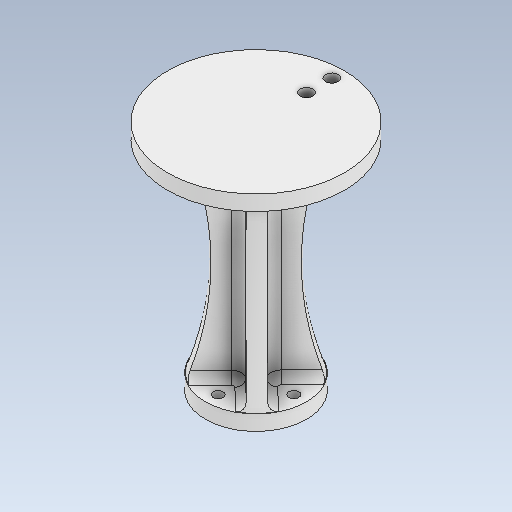
# Autodesk Inventor part: Load cell support
Saved by Autodesk Inventor 2026.2 (Build 302298010, 298A)
## iProperties
Created: 2026-04-30
Part Number: Load cell support
Material: ABS 플라스틱
Document SubType Name: Modeling
Designer: khw
Density: 1.06 g/cm^3
Appearance: 매끄러움 - 흰색
Author: khw
Autodesk Inventor part; units mm, degrees
ref_plane "YZ Plane" through (0, 0, 0) normal (1, 0, 0) x (0, 1, 0)
ref_plane "XZ Plane" through (0, 0, 0) normal (0, 1, 0) x (-1, 0, 0)
sketch "스케치1" plane through (0, 0, 0) normal (0, 1, 0) x (-1, 0, 0)
  circle A0 centre (0, 0) radius 20
  circle A1 centre (15, 0) radius 2
  line L0 (0, 0) -> (15, 0) construction
  circle A2 centre (0, 15) radius 2
  line L1 (0, 0) -> (0, 15) construction
  circle A3 centre (-15, 0) radius 2
  line L2 (0, 0) -> (-15, 0) construction
  circle A4 centre (0, -15) radius 2
  line L3 (0, 0) -> (0, -15) construction
  dimension "d0" = 4
  dimension "d1" = 15
  dimension "d2" = 40
  dimension "d5" = 360
  constraints: 8 end point, 5 centre point, 3 coincident, 1 horizontal, 15 other
  measures "d0" diameter of A1
  measures "d1" distance of L0.end point (0, 0)
  measures "d2" diameter of A0
extrude "돌출1" add sketch "스케치1" along normal blind 6
sketch "스케치2" plane through (0, 6, 0) normal (0, 1, 0) x (1, 0, 0)
  circle A0 centre (0, 0) radius 20 projected
  line L0 (-13.9405, -14.3409) -> (13.9405, 14.3409) construction
  line L1 (-11.6317, -16.2697) -> (15.9339, 12.0876)
  line L2 (-15.9339, -12.0876) -> (11.6317, 16.2697)
  line L3 (14.3409, -13.9405) -> (-14.3409, 13.9405) construction
  line L4 (16.2697, -11.6317) -> (-12.0876, 15.9339)
  line L5 (12.0876, -15.9339) -> (-16.2697, 11.6317)
  line L6 (13.9405, 14.3409) -> (-13.9405, -14.3409) construction
  line L7 (11.6317, 16.2697) -> (-15.9339, -12.0876)
  line L8 (15.9339, 12.0876) -> (-11.6317, -16.2697)
  line L9 (-14.3409, 13.9405) -> (14.3409, -13.9405) construction
  line L10 (-16.2697, 11.6317) -> (12.0876, -15.9339)
  line L11 (-12.0876, 15.9339) -> (16.2697, -11.6317)
  point P0 (-4.2422, -0.0601)
  point P1 (0.0601, -4.2422)
  point P2 (4.2422, 0.0601)
  point P3 (11.6317, 16.2697)
  point P4 (-0.0601, 4.2422)
  point P5 (-16.2697, 11.6317)
  dimension "d9" = 40
  dimension "d10" = 3
  dimension "d13" = 360
  constraints: 24 end point, 4 point on circle, 2 coincident, 2 symmetric about line, 1 parallel, 43 other
  measures "d9" distance of L0.start L0.end
  measures "d10" distance between parallel lines of L0 L1
extrude "돌출2" add sketch "스케치2" along normal blind 80 contours L1 L4 L2 A0 | A0 L5 L1 L4 | L1 L5 L2 L4 | L4 L2 L5 A0 | L1 A0 L2 L5
sketch "스케치3" plane through (0, 86, 0) normal (0, 1, 0) x (1, 0, 0)
  circle A0 centre (0, 0) radius 35
  circle A1 centre (0, 0) radius 20 projected
  line L0 (0, 0) -> (0, 35)
  circle A2 centre (0, 20) radius 2.5
  circle A3 centre (0, 30) radius 2.5
  dimension "d21" = 70
  dimension "d17" = 5
  dimension "d18" = 5
  dimension "d19" = 10
  dimension "d20" = 20
  constraints: 2 centre point, 2 end point, 2 point on line, 1 coincident, 1 vertical, 1 vertical alignment, 2 other
  measures "d17" diameter of A2
  measures "d18" diameter of A3
  measures "d19" distance of A2.centre A3.centre
  measures "d20" distance of point (0, 0) A2.centre
extrude "돌출3" add sketch "스케치3" along normal blind 6 contours A0 | A2 A1
ref_plane "작업 평면1" through (-2.0911, 6, 2.1511) normal (0.717, 0, 0.697) x (0.697, 0, -0.717)
sketch "스케치4" plane through (-2.0911, 6, 2.1511) normal (0.717, 0, 0.697) x (0.697, 0, -0.717)
  arc A0 (-16.7737, 0) -> (-16.7737, 80) centre (-131.4904, 40) ccw
  line L0 (0, 80) -> (0, 0)
  line L1 (-16.7737, 0) -> (-16.7737, 80)
  line L2 (3, 0) -> (3, 80)
  line L3 (6, 80) -> (0, 80) projected
  line L4 (-16.7737, 0) -> (-45.3544, 0)
  line L5 (-45.3544, 0) -> (-45.3544, 80)
  line L6 (-45.3544, 80) -> (-16.7737, 80)
  line L7 (-16.7737, 80) -> (-16.7737, 0)
  point P0 (3, -6)
  point P1 (-10, 40)
  dimension "d25" = 20
  constraints: 14 end point, 3 parallel, 3 point on circle, 1 centre point, 1 horizontal, 1 midpoint, 1 perpendicular, 1 vertical
  measures "d25" diameter of point (-10, 40) L0
revolve "회전1" cut sketch "스케치4" angle 360 about axis through (0, 6, 0) along (0, 1, 0)
fillet "모깎기1" radius 4 4 edges at (0.0601, 46, 4.2422) (-4.2422, 46, 0.0601) (-0.0601, 46, -4.2422) (4.2422, 46, -0.0601)
fillet "모깎기2" radius 3 28 edges at (5.8989, 6, -0.0835) (11.4024, 6, -7.4258) (11.608, 6, 7.1001) (0.0835, 6, 5.8989) (7.4258, 6, 11.4024) (-7.1001, 6, 11.608) (-0.0835, 6, -5.8989) (7.1001, 6, -11.608) (-7.4258, 6, -11.4024) (-11.608, 6, -7.1001) (-11.4024, 6, 7.4258) (-5.8989, 6, 0.0835) (-5.8989, 86, 0.0835) (-11.608, 86, -7.1001) (-11.4024, 86, 7.4258) (-0.0835, 86, -5.8989) (-7.4258, 86, -11.4024) (7.1001, 86, -11.608) (5.8989, 86, -0.0835) (11.608, 86, 7.1001) (11.4024, 86, -7.4258) (-13.7828, 86, 14.1787) (13.7828, 86, -14.1787) (-14.1787, 86, -13.7828) (14.1787, 86, 13.7828) (0.0835, 86, 5.8989) (-7.1001, 86, 11.608) (7.4258, 86, 11.4024)
